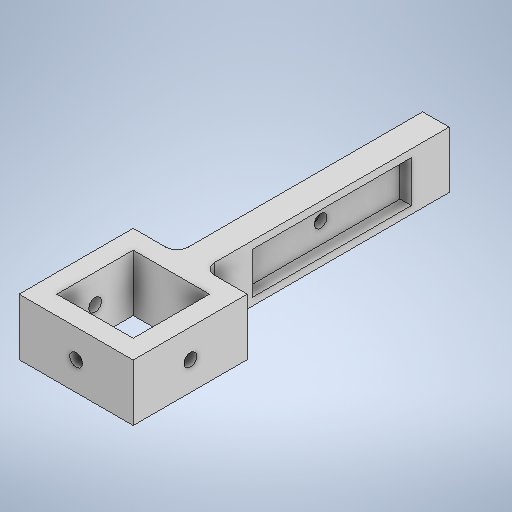
# Autodesk Inventor part: SUJETADOR_CAMARA_NUEVO
Saved by Autodesk Inventor 2025.3 (Build 293356030, 356C)
## iProperties
Created: 2026-05-21
Part Number: SUJETADOR_CAMARA_NUEVO
Material: Generic
Document SubType Name: Modeling
Designer: pablo
Density: 1 g/cm^3
Appearance: Default
Author: pablo
Autodesk Inventor part; units mm, degrees
ref_plane "YZ Plane" through (0, 0, 0) normal (1, 0, 0) x (0, 1, 0)
ref_plane "XZ Plane" through (0, 0, 0) normal (0, 1, 0) x (-1, 0, 0)
ref_plane "XY Plane" through (0, 0, 0) normal (0, 0, 1) x (1, 0, 0)
sketch "Sketch1" plane through (0, 0, 0) normal (0, 1, 0) x (-1, 0, 0)
  line L0 (0, 0) -> (20.2, 0)
  line L1 (20.2, 0) -> (20.2, -20.2)
  line L2 (20.2, -20.2) -> (0, -20.2)
  line L3 (0, -20.2) -> (0, 0)
  line L4 (25.2, 5) -> (-5, 5)
  line L5 (-5, 5) -> (-5, -25.2)
  line L6 (-5, -25.2) -> (25.2, -25.2)
  line L7 (25.2, -25.2) -> (25.2, 5)
  dimension "d0" = 20.2
  dimension "d1" = 5
  dimension "d2" = 5
  dimension "d3" = 5
  dimension "d4" = 5
  constraints: 16 end point, 4 parallel, 3 perpendicular, 2 horizontal
  measures "d0" distance of L1.end L2.end
  measures "d1" distance between parallel lines of L5 L3
  measures "d2" distance between parallel lines of L6 L2
  measures "d3" distance between parallel lines of L1 L7
  measures "d4" distance between parallel lines of L0 L4
extrude "Extrusion1" add sketch "Sketch1" along normal blind 15
sketch "Sketch2" plane through (5, 0, 5) normal (1, 0, 0) x (0, 0, -1)
  line L0 (0, 0) -> (30.2, 0) projected
  line L1 (30.2, 0) -> (30.2, 15) projected
  line L2 (0, 15) -> (30.2, 15) projected
  line L3 (0, 0) -> (0, 15) projected
  point P0 (5, 0)
  point P1 (15.1, 7.5)
  point P2 (15.1, 15)
  point P3 (0, 7.5)
  constraints: 2 midpoint, 1 horizontal alignment, 1 vertical alignment
hole "Hole1" at (5, 7.5, -10.1) direction (-1, 0, 0) diameter 3.4 depth 30.2
sketch "Sketch3" plane through (-25.2, 0, 5) normal (0, 0, 1) x (1, 0, 0)
  line L0 (0, 0) -> (30.2, 0) projected
  line L1 (30.2, 0) -> (30.2, 15) projected
  line L2 (0, 15) -> (30.2, 15) projected
  line L3 (0, 0) -> (0, 15) projected
  point P0 (25.2, 0)
  point P1 (15.1, 7.5)
  point P2 (0, 7.5)
  point P3 (15.1, 15)
  constraints: 2 midpoint, 1 horizontal alignment, 1 vertical alignment
hole "Hole2" at (-10.1, 7.5, 5) direction (0, 0, -1) diameter 3.4 depth 5
sketch "Sketch4" plane through (5, 0, -25.2) normal (0, 0, -1) x (-1, 0, 0)
  line L0 (0, 0) -> (30.2, 0) projected
  line L1 (30.2, 0) -> (30.2, 15) projected
  line L2 (0, 15) -> (30.2, 15) projected
  line L3 (0, 0) -> (0, 15) projected
  line L4 (11.6, 0) -> (18.6, 0)
  line L5 (18.6, 0) -> (18.6, 15)
  line L6 (18.6, 15) -> (11.6, 15)
  line L7 (11.6, 15) -> (11.6, 0)
  point P0 (5, 0)
  point P1 (15.1, 15)
  point P2 (15.1, 15)
  dimension "d21" = 7
  constraints: 8 end point, 2 midpoint, 2 parallel, 2 point on line, 1 coincident, 1 horizontal, 1 perpendicular
  measures "d21" distance between parallel lines of L5 L7
extrude "Extrusion2" add sketch "Sketch4" along normal blind 65 contours L7 L2 L5 L0
fillet "Fillet1" radius 3 2 edges at (-6.6, 7.5, -25.2) (-13.6, 7.5, -25.2)
sketch "Sketch5" plane through (-6.6, 0, -90.2) normal (1, 0, 0) x (0, 0, -1)
  line L0 (-62, 0) -> (-62, 15) projected
  line L1 (-62, 0) -> (0, 0) projected
  line L2 (0, 15) -> (0, 0) projected
  line L3 (-62, 15) -> (0, 15) projected
  line L4 (0, 2) -> (-62, 2)
  line L5 (-62, 2) -> (-62, 13)
  line L6 (-62, 13) -> (0, 13)
  line L7 (0, 13) -> (0, 2)
  line L8 (-52, 13) -> (-52, 2)
  line L9 (-10, 13) -> (-10, 2)
  point P0 (-90.2, 0)
  point P1 (0, 7.5)
  point P2 (0, 7.5)
  point P3 (-31, 13)
  dimension "d25" = 11
  dimension "d26" = 42
  dimension "d27" = 21
  constraints: 12 end point, 6 point on line, 3 midpoint, 3 perpendicular, 2 parallel, 1 coincident, 1 horizontal
  measures "d25" distance between parallel lines of L4 L6
  measures "d26" distance between parallel lines of L8 L9
  measures "d27" distance from line of point (-31, 13) L8
extrude "Extrusion3" cut sketch "Sketch5" against normal blind 3 contours L8 L6 L9 L4
sketch "Sketch6" plane through (-9.6, 0, -90.2) normal (1, 0, 0) x (0, 0, -1)
  line L0 (-52, 13) -> (-10, 13) projected
  line L1 (-52, 2) -> (-52, 13) projected
  line L2 (-10, 2) -> (-52, 2) projected
  line L3 (-10, 13) -> (-10, 2) projected
  line L4 (-10, 13) -> (-10, 2) projected
  line L5 (-52, 13) -> (-10, 13) projected
  point P0 (-90.2, 0)
  point P1 (-31, 7.5)
  point P2 (-10, 7.5)
  point P3 (-31, 13)
  constraints: 2 midpoint, 1 horizontal alignment, 1 vertical alignment
hole "Hole3" at (-9.6, 7.5, -59.2) direction (-1, 0, 0) diameter 3.4 depth 4
sketch "Sketch7" plane through (-13.6, 0, -90.2) normal (-1, 0, 0) x (0, 0, 1)
  circle A0 centre (31, 7.5) radius 1.7 projected
  line L0 (62, 15) -> (62, 0) projected
  line L1 (62, 15) -> (0, 15) projected
  line L2 (0, 0) -> (0, 15) projected
  line L3 (62, 0) -> (0, 0) projected
  circle A1 centre (31, 7.5) radius 4
  point P0 (90.2, 0)
  dimension "d37" = 8
  constraints: 1 centre point, 1 coincident
  measures "d37" diameter of A1
extrude "Extrusion4" cut sketch "Sketch7" against normal blind 2 contours A1
equation "\"d27\" = 0.5 * d26"
body "Solid1"
